Autodesk Fusion 360 part; units mm, degrees
(part 5 of 5)
sketch "cheekL_pb12" plane through (128.9714, 0, 0) normal (1, 0, 0) x (0, 0, -1)
  line L0 (14.535, -22.1731) -> (11.628, -22.1731)
  line L1 (11.628, -22.1731) -> (8.721, -22.1731)
  line L2 (8.721, -22.1731) -> (5.814, -22.1731)
  line L3 (5.814, -22.1731) -> (2.907, -22.1731)
  line L4 (2.907, -22.1731) -> (0, -22.1731)
  line L5 (0, -22.1731) -> (-2.907, -22.1731)
  line L6 (-2.907, -22.1731) -> (-5.814, -22.1731)
  line L7 (-5.814, -22.1731) -> (-8.721, -22.1731)
  line L8 (-8.721, -22.1731) -> (-11.628, -22.1731)
  line L9 (-11.628, -22.1731) -> (-14.535, -22.1731)
  line L10 (-14.535, -22.1731) -> (-14.535, -20.1731)
  line L11 (-14.535, -20.1731) -> (-11.628, -20.1731)
  line L12 (-11.628, -20.1731) -> (-8.721, -20.1731)
  line L13 (-8.721, -20.1731) -> (-5.814, -20.1731)
  line L14 (-5.814, -20.1731) -> (-2.907, -20.1731)
  line L15 (-2.907, -20.1731) -> (0, -20.1731)
  line L16 (0, -20.1731) -> (2.907, -20.1731)
  line L17 (2.907, -20.1731) -> (5.814, -20.1731)
  line L18 (5.814, -20.1731) -> (8.721, -20.1731)
  line L19 (8.721, -20.1731) -> (11.628, -20.1731)
  line L20 (11.628, -20.1731) -> (14.535, -20.1731)
  line L21 (14.535, -20.1731) -> (14.535, -22.1731)
loft "Loft67" add profiles "cheekL_pa12", "cheekL_pb12" section 1 section 2 separate body makes body 67
ref_plane "WorkPlane135" through (128.1714, 0, 0) normal (1, 0, 0) x (0, 1, 0)
sketch "cheekL_pa13" plane through (128.1714, 0, 0) normal (1, 0, 0) x (0, 0, -1)
  line L0 (14.535, -22.1731) -> (11.628, -22.1731)
  line L1 (11.628, -22.1731) -> (8.721, -22.1731)
  line L2 (8.721, -22.1731) -> (5.814, -22.1731)
  line L3 (5.814, -22.1731) -> (2.907, -22.1731)
  line L4 (2.907, -22.1731) -> (0, -22.1731)
  line L5 (0, -22.1731) -> (-2.907, -22.1731)
  line L6 (-2.907, -22.1731) -> (-5.814, -22.1731)
  line L7 (-5.814, -22.1731) -> (-8.721, -22.1731)
  line L8 (-8.721, -22.1731) -> (-11.628, -22.1731)
  line L9 (-11.628, -22.1731) -> (-14.535, -22.1731)
  line L10 (-14.535, -22.1731) -> (-14.535, -20.1731)
  line L11 (-14.535, -20.1731) -> (-11.628, -20.1731)
  line L12 (-11.628, -20.1731) -> (-8.721, -20.1731)
  line L13 (-8.721, -20.1731) -> (-5.814, -20.1731)
  line L14 (-5.814, -20.1731) -> (-2.907, -20.1731)
  line L15 (-2.907, -20.1731) -> (0, -20.1731)
  line L16 (0, -20.1731) -> (2.907, -20.1731)
  line L17 (2.907, -20.1731) -> (5.814, -20.1731)
  line L18 (5.814, -20.1731) -> (8.721, -20.1731)
  line L19 (8.721, -20.1731) -> (11.628, -20.1731)
  line L20 (11.628, -20.1731) -> (14.535, -20.1731)
  line L21 (14.535, -20.1731) -> (14.535, -22.1731)
ref_plane "WorkPlane136" through (133.2571, 0, 0) normal (1, 0, 0) x (0, 1, 0)
sketch "cheekL_pb13" plane through (133.2571, 0, 0) normal (1, 0, 0) x (0, 0, -1)
  line L0 (12.9035, -20.1869) -> (10.3228, -20.1869)
  line L1 (10.3228, -20.1869) -> (7.7421, -20.1869)
  line L2 (7.7421, -20.1869) -> (5.1614, -20.1869)
  line L3 (5.1614, -20.1869) -> (2.5807, -20.1869)
  line L4 (2.5807, -20.1869) -> (0, -20.1869)
  line L5 (0, -20.1869) -> (-2.5807, -20.1869)
  line L6 (-2.5807, -20.1869) -> (-5.1614, -20.1869)
  line L7 (-5.1614, -20.1869) -> (-7.7421, -20.1869)
  line L8 (-7.7421, -20.1869) -> (-10.3228, -20.1869)
  line L9 (-10.3228, -20.1869) -> (-12.9035, -20.1869)
  line L10 (-12.9035, -20.1869) -> (-12.9035, -18.1869)
  line L11 (-12.9035, -18.1869) -> (-10.3228, -18.1869)
  line L12 (-10.3228, -18.1869) -> (-7.7421, -18.1869)
  line L13 (-7.7421, -18.1869) -> (-5.1614, -18.1869)
  line L14 (-5.1614, -18.1869) -> (-2.5807, -18.1869)
  line L15 (-2.5807, -18.1869) -> (0, -18.1869)
  line L16 (0, -18.1869) -> (2.5807, -18.1869)
  line L17 (2.5807, -18.1869) -> (5.1614, -18.1869)
  line L18 (5.1614, -18.1869) -> (7.7421, -18.1869)
  line L19 (7.7421, -18.1869) -> (10.3228, -18.1869)
  line L20 (10.3228, -18.1869) -> (12.9035, -18.1869)
  line L21 (12.9035, -18.1869) -> (12.9035, -20.1869)
loft "Loft68" add profiles "cheekL_pa13", "cheekL_pb13" section 1 section 2 separate body makes body 68
ref_plane "WorkPlane137" through (132.4571, 0, 0) normal (1, 0, 0) x (0, 1, 0)
sketch "cheekL_pa14" plane through (132.4571, 0, 0) normal (1, 0, 0) x (0, 0, -1)
  line L0 (12.9035, -20.1869) -> (10.3228, -20.1869)
  line L1 (10.3228, -20.1869) -> (7.7421, -20.1869)
  line L2 (7.7421, -20.1869) -> (5.1614, -20.1869)
  line L3 (5.1614, -20.1869) -> (2.5807, -20.1869)
  line L4 (2.5807, -20.1869) -> (0, -20.1869)
  line L5 (0, -20.1869) -> (-2.5807, -20.1869)
  line L6 (-2.5807, -20.1869) -> (-5.1614, -20.1869)
  line L7 (-5.1614, -20.1869) -> (-7.7421, -20.1869)
  line L8 (-7.7421, -20.1869) -> (-10.3228, -20.1869)
  line L9 (-10.3228, -20.1869) -> (-12.9035, -20.1869)
  line L10 (-12.9035, -20.1869) -> (-12.9035, -18.1869)
  line L11 (-12.9035, -18.1869) -> (-10.3228, -18.1869)
  line L12 (-10.3228, -18.1869) -> (-7.7421, -18.1869)
  line L13 (-7.7421, -18.1869) -> (-5.1614, -18.1869)
  line L14 (-5.1614, -18.1869) -> (-2.5807, -18.1869)
  line L15 (-2.5807, -18.1869) -> (0, -18.1869)
  line L16 (0, -18.1869) -> (2.5807, -18.1869)
  line L17 (2.5807, -18.1869) -> (5.1614, -18.1869)
  line L18 (5.1614, -18.1869) -> (7.7421, -18.1869)
  line L19 (7.7421, -18.1869) -> (10.3228, -18.1869)
  line L20 (10.3228, -18.1869) -> (12.9035, -18.1869)
  line L21 (12.9035, -18.1869) -> (12.9035, -20.1869)
ref_plane "WorkPlane138" through (137.5429, 0, 0) normal (1, 0, 0) x (0, 1, 0)
sketch "cheekL_pb14" plane through (137.5429, 0, 0) normal (1, 0, 0) x (0, 0, -1)
  line L0 (11.3531, -18.2995) -> (9.0825, -18.2995)
  line L1 (9.0825, -18.2995) -> (6.8119, -18.2995)
  line L2 (6.8119, -18.2995) -> (4.5413, -18.2995)
  line L3 (4.5413, -18.2995) -> (2.2706, -18.2995)
  line L4 (2.2706, -18.2995) -> (0, -18.2995)
  line L5 (0, -18.2995) -> (-2.2706, -18.2995)
  line L6 (-2.2706, -18.2995) -> (-4.5413, -18.2995)
  line L7 (-4.5413, -18.2995) -> (-6.8119, -18.2995)
  line L8 (-6.8119, -18.2995) -> (-9.0825, -18.2995)
  line L9 (-9.0825, -18.2995) -> (-11.3531, -18.2995)
  line L10 (-11.3531, -18.2995) -> (-11.3531, -16.2995)
  line L11 (-11.3531, -16.2995) -> (-9.0825, -16.2995)
  line L12 (-9.0825, -16.2995) -> (-6.8119, -16.2995)
  line L13 (-6.8119, -16.2995) -> (-4.5413, -16.2995)
  line L14 (-4.5413, -16.2995) -> (-2.2706, -16.2995)
  line L15 (-2.2706, -16.2995) -> (0, -16.2995)
  line L16 (0, -16.2995) -> (2.2706, -16.2995)
  line L17 (2.2706, -16.2995) -> (4.5413, -16.2995)
  line L18 (4.5413, -16.2995) -> (6.8119, -16.2995)
  line L19 (6.8119, -16.2995) -> (9.0825, -16.2995)
  line L20 (9.0825, -16.2995) -> (11.3531, -16.2995)
  line L21 (11.3531, -16.2995) -> (11.3531, -18.2995)
loft "Loft69" add profiles "cheekL_pa14", "cheekL_pb14" section 1 section 2 separate body makes body 69
ref_plane "WorkPlane139" through (136.7429, 0, 0) normal (1, 0, 0) x (0, 1, 0)
sketch "cheekL_pa15" plane through (136.7429, 0, 0) normal (1, 0, 0) x (0, 0, -1)
  line L0 (11.3531, -18.2995) -> (9.0825, -18.2995)
  line L1 (9.0825, -18.2995) -> (6.8119, -18.2995)
  line L2 (6.8119, -18.2995) -> (4.5413, -18.2995)
  line L3 (4.5413, -18.2995) -> (2.2706, -18.2995)
  line L4 (2.2706, -18.2995) -> (0, -18.2995)
  line L5 (0, -18.2995) -> (-2.2706, -18.2995)
  line L6 (-2.2706, -18.2995) -> (-4.5413, -18.2995)
  line L7 (-4.5413, -18.2995) -> (-6.8119, -18.2995)
  line L8 (-6.8119, -18.2995) -> (-9.0825, -18.2995)
  line L9 (-9.0825, -18.2995) -> (-11.3531, -18.2995)
  line L10 (-11.3531, -18.2995) -> (-11.3531, -16.2995)
  line L11 (-11.3531, -16.2995) -> (-9.0825, -16.2995)
  line L12 (-9.0825, -16.2995) -> (-6.8119, -16.2995)
  line L13 (-6.8119, -16.2995) -> (-4.5413, -16.2995)
  line L14 (-4.5413, -16.2995) -> (-2.2706, -16.2995)
  line L15 (-2.2706, -16.2995) -> (0, -16.2995)
  line L16 (0, -16.2995) -> (2.2706, -16.2995)
  line L17 (2.2706, -16.2995) -> (4.5413, -16.2995)
  line L18 (4.5413, -16.2995) -> (6.8119, -16.2995)
  line L19 (6.8119, -16.2995) -> (9.0825, -16.2995)
  line L20 (9.0825, -16.2995) -> (11.3531, -16.2995)
  line L21 (11.3531, -16.2995) -> (11.3531, -18.2995)
ref_plane "WorkPlane140" through (141.8286, 0, 0) normal (1, 0, 0) x (0, 1, 0)
sketch "cheekL_pb15" plane through (141.8286, 0, 0) normal (1, 0, 0) x (0, 0, -1)
  line L0 (9.8605, -16.4823) -> (7.8884, -16.4823)
  line L1 (7.8884, -16.4823) -> (5.9163, -16.4823)
  line L2 (5.9163, -16.4823) -> (3.9442, -16.4823)
  line L3 (3.9442, -16.4823) -> (1.9721, -16.4823)
  line L4 (1.9721, -16.4823) -> (0, -16.4823)
  line L5 (0, -16.4823) -> (-1.9721, -16.4823)
  line L6 (-1.9721, -16.4823) -> (-3.9442, -16.4823)
  line L7 (-3.9442, -16.4823) -> (-5.9163, -16.4823)
  line L8 (-5.9163, -16.4823) -> (-7.8884, -16.4823)
  line L9 (-7.8884, -16.4823) -> (-9.8605, -16.4823)
  line L10 (-9.8605, -16.4823) -> (-9.8605, -14.4823)
  line L11 (-9.8605, -14.4823) -> (-7.8884, -14.4823)
  line L12 (-7.8884, -14.4823) -> (-5.9163, -14.4823)
  line L13 (-5.9163, -14.4823) -> (-3.9442, -14.4823)
  line L14 (-3.9442, -14.4823) -> (-1.9721, -14.4823)
  line L15 (-1.9721, -14.4823) -> (0, -14.4823)
  line L16 (0, -14.4823) -> (1.9721, -14.4823)
  line L17 (1.9721, -14.4823) -> (3.9442, -14.4823)
  line L18 (3.9442, -14.4823) -> (5.9163, -14.4823)
  line L19 (5.9163, -14.4823) -> (7.8884, -14.4823)
  line L20 (7.8884, -14.4823) -> (9.8605, -14.4823)
  line L21 (9.8605, -14.4823) -> (9.8605, -16.4823)
loft "Loft70" add profiles "cheekL_pa15", "cheekL_pb15" section 1 section 2 separate body makes body 70
ref_plane "WorkPlane141" through (141.0286, 0, 0) normal (1, 0, 0) x (0, 1, 0)
sketch "cheekL_pa16" plane through (141.0286, 0, 0) normal (1, 0, 0) x (0, 0, -1)
  line L0 (9.8605, -16.4823) -> (7.8884, -16.4823)
  line L1 (7.8884, -16.4823) -> (5.9163, -16.4823)
  line L2 (5.9163, -16.4823) -> (3.9442, -16.4823)
  line L3 (3.9442, -16.4823) -> (1.9721, -16.4823)
  line L4 (1.9721, -16.4823) -> (0, -16.4823)
  line L5 (0, -16.4823) -> (-1.9721, -16.4823)
  line L6 (-1.9721, -16.4823) -> (-3.9442, -16.4823)
  line L7 (-3.9442, -16.4823) -> (-5.9163, -16.4823)
  line L8 (-5.9163, -16.4823) -> (-7.8884, -16.4823)
  line L9 (-7.8884, -16.4823) -> (-9.8605, -16.4823)
  line L10 (-9.8605, -16.4823) -> (-9.8605, -14.4823)
  line L11 (-9.8605, -14.4823) -> (-7.8884, -14.4823)
  line L12 (-7.8884, -14.4823) -> (-5.9163, -14.4823)
  line L13 (-5.9163, -14.4823) -> (-3.9442, -14.4823)
  line L14 (-3.9442, -14.4823) -> (-1.9721, -14.4823)
  line L15 (-1.9721, -14.4823) -> (0, -14.4823)
  line L16 (0, -14.4823) -> (1.9721, -14.4823)
  line L17 (1.9721, -14.4823) -> (3.9442, -14.4823)
  line L18 (3.9442, -14.4823) -> (5.9163, -14.4823)
  line L19 (5.9163, -14.4823) -> (7.8884, -14.4823)
  line L20 (7.8884, -14.4823) -> (9.8605, -14.4823)
  line L21 (9.8605, -14.4823) -> (9.8605, -16.4823)
ref_plane "WorkPlane142" through (146.1143, 0, 0) normal (1, 0, 0) x (0, 1, 0)
sketch "cheekL_pb16" plane through (146.1143, 0, 0) normal (1, 0, 0) x (0, 0, -1)
  line L0 (8.4123, -14.7193) -> (6.7298, -14.7193)
  line L1 (6.7298, -14.7193) -> (5.0474, -14.7193)
  line L2 (5.0474, -14.7193) -> (3.3649, -14.7193)
  line L3 (3.3649, -14.7193) -> (1.6825, -14.7193)
  line L4 (1.6825, -14.7193) -> (0, -14.7193)
  line L5 (0, -14.7193) -> (-1.6825, -14.7193)
  line L6 (-1.6825, -14.7193) -> (-3.3649, -14.7193)
  line L7 (-3.3649, -14.7193) -> (-5.0474, -14.7193)
  line L8 (-5.0474, -14.7193) -> (-6.7298, -14.7193)
  line L9 (-6.7298, -14.7193) -> (-8.4123, -14.7193)
  line L10 (-8.4123, -14.7193) -> (-8.4123, -12.7193)
  line L11 (-8.4123, -12.7193) -> (-6.7298, -12.7193)
  line L12 (-6.7298, -12.7193) -> (-5.0474, -12.7193)
  line L13 (-5.0474, -12.7193) -> (-3.3649, -12.7193)
  line L14 (-3.3649, -12.7193) -> (-1.6825, -12.7193)
  line L15 (-1.6825, -12.7193) -> (0, -12.7193)
  line L16 (0, -12.7193) -> (1.6825, -12.7193)
  line L17 (1.6825, -12.7193) -> (3.3649, -12.7193)
  line L18 (3.3649, -12.7193) -> (5.0474, -12.7193)
  line L19 (5.0474, -12.7193) -> (6.7298, -12.7193)
  line L20 (6.7298, -12.7193) -> (8.4123, -12.7193)
  line L21 (8.4123, -12.7193) -> (8.4123, -14.7193)
loft "Loft71" add profiles "cheekL_pa16", "cheekL_pb16" section 1 section 2 separate body makes body 71
ref_plane "WorkPlane143" through (145.3143, 0, 0) normal (1, 0, 0) x (0, 1, 0)
sketch "cheekL_pa17" plane through (145.3143, 0, 0) normal (1, 0, 0) x (0, 0, -1)
  line L0 (8.4123, -14.7193) -> (6.7298, -14.7193)
  line L1 (6.7298, -14.7193) -> (5.0474, -14.7193)
  line L2 (5.0474, -14.7193) -> (3.3649, -14.7193)
  line L3 (3.3649, -14.7193) -> (1.6825, -14.7193)
  line L4 (1.6825, -14.7193) -> (0, -14.7193)
  line L5 (0, -14.7193) -> (-1.6825, -14.7193)
  line L6 (-1.6825, -14.7193) -> (-3.3649, -14.7193)
  line L7 (-3.3649, -14.7193) -> (-5.0474, -14.7193)
  line L8 (-5.0474, -14.7193) -> (-6.7298, -14.7193)
  line L9 (-6.7298, -14.7193) -> (-8.4123, -14.7193)
  line L10 (-8.4123, -14.7193) -> (-8.4123, -12.7193)
  line L11 (-8.4123, -12.7193) -> (-6.7298, -12.7193)
  line L12 (-6.7298, -12.7193) -> (-5.0474, -12.7193)
  line L13 (-5.0474, -12.7193) -> (-3.3649, -12.7193)
  line L14 (-3.3649, -12.7193) -> (-1.6825, -12.7193)
  line L15 (-1.6825, -12.7193) -> (0, -12.7193)
  line L16 (0, -12.7193) -> (1.6825, -12.7193)
  line L17 (1.6825, -12.7193) -> (3.3649, -12.7193)
  line L18 (3.3649, -12.7193) -> (5.0474, -12.7193)
  line L19 (5.0474, -12.7193) -> (6.7298, -12.7193)
  line L20 (6.7298, -12.7193) -> (8.4123, -12.7193)
  line L21 (8.4123, -12.7193) -> (8.4123, -14.7193)
ref_plane "WorkPlane144" through (150, 0, 0) normal (1, 0, 0) x (0, 1, 0)
sketch "cheekL_pb17" plane through (150, 0, 0) normal (1, 0, 0) x (0, 0, -1)
  line L0 (7, -13) -> (5.6, -13)
  line L1 (5.6, -13) -> (4.2, -13)
  line L2 (4.2, -13) -> (2.8, -13)
  line L3 (2.8, -13) -> (1.4, -13)
  line L4 (1.4, -13) -> (0, -13)
  line L5 (0, -13) -> (-1.4, -13)
  line L6 (-1.4, -13) -> (-2.8, -13)
  line L7 (-2.8, -13) -> (-4.2, -13)
  line L8 (-4.2, -13) -> (-5.6, -13)
  line L9 (-5.6, -13) -> (-7, -13)
  line L10 (-7, -13) -> (-7, -11)
  line L11 (-7, -11) -> (-5.6, -11)
  line L12 (-5.6, -11) -> (-4.2, -11)
  line L13 (-4.2, -11) -> (-2.8, -11)
  line L14 (-2.8, -11) -> (-1.4, -11)
  line L15 (-1.4, -11) -> (0, -11)
  line L16 (0, -11) -> (1.4, -11)
  line L17 (1.4, -11) -> (2.8, -11)
  line L18 (2.8, -11) -> (4.2, -11)
  line L19 (4.2, -11) -> (5.6, -11)
  line L20 (5.6, -11) -> (7, -11)
  line L21 (7, -11) -> (7, -13)
loft "Loft72" add profiles "cheekL_pa17", "cheekL_pb17" section 1 section 2 separate body makes body 72
named bodies: "roof_s00", "roof_s01", "roof_s02", "roof_s03", "roof_s04", "roof_s05", "roof_s06", "roof_s07", "roof_s08", "roof_s09", "roof_s10", "roof_s11", "roof_s12", "roof_s13", "roof_s14", "roof_s15", "roof_s16", "roof_s17", "belly_s00", "belly_s01", "belly_s02", "belly_s03", "belly_s04", "belly_s05", "belly_s06", "belly_s07", "belly_s08", "belly_s09", "belly_s10", "belly_s11", "belly_s12", "belly_s13", "belly_s14", "belly_s15", "belly_s16", "belly_s17", "cheekR_s00", "cheekR_s01", "cheekR_s02", "cheekR_s03", "cheekR_s04", "cheekR_s05", "cheekR_s06", "cheekR_s07", "cheekR_s08", "cheekR_s09", "cheekR_s10", "cheekR_s11", "cheekR_s12", "cheekR_s13", "cheekR_s14", "cheekR_s15", "cheekR_s16", "cheekR_s17", "cheekL_s00", "cheekL_s01", "cheekL_s02", "cheekL_s03", "cheekL_s04", "cheekL_s05", "cheekL_s06", "cheekL_s07", "cheekL_s08", "cheekL_s09", "cheekL_s10", "cheekL_s11", "cheekL_s12", "cheekL_s13", "cheekL_s14", "cheekL_s15", "cheekL_s16", "cheekL_s17"
